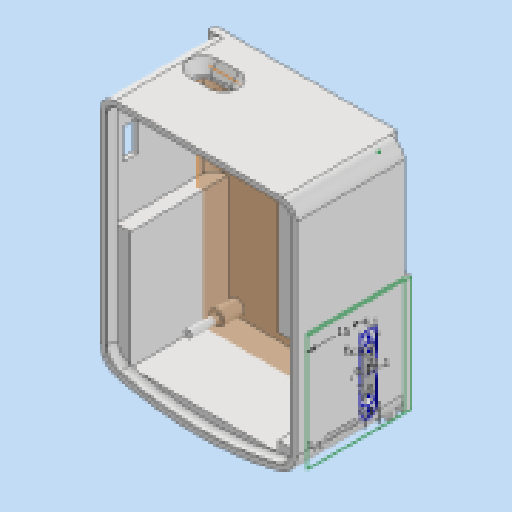
# Autodesk Inventor part: Pieza5
Saved by Autodesk Inventor 2026.3 (Build 303398000, 398)
## iProperties
Created: 2026-11-10
Part Number: Pieza5
Material: Genérico
Document SubType Name: Modeling
Designer: Hp
Density: 1 g/cm^3
Appearance: Valor por defecto
Author: Hp
Autodesk Inventor part; units mm, degrees
(part 1 of 2)
ref_plane "YZ Plane" through (0, 0, 0) normal (1, 0, 0) x (0, 1, 0)
ref_plane "XZ Plane" through (0, 0, 0) normal (0, 1, 0) x (-1, 0, 0)
ref_plane "Plano de trabajo1" through (0, 0, 0) normal (0, 0, 1) x (1, 0, 0)
sketch "Boceto1" plane through (0, 0, 0) normal (0, 0, 1) x (1, 0, 0)
  line L0 (-44, -6) -> (-4, -6)
  line L1 (-44, -66) -> (-44, -6)
  line L2 (-4, -66) -> (-44, -66)
  line L3 (-4, -6) -> (-4, -66)
  circle A0 centre (-40.51, -14.25) radius 0.55
  circle A1 centre (-40.51, -16.79) radius 0.55
  circle A2 centre (-40.51, -19.33) radius 0.55
  circle A3 centre (-40.51, -21.87) radius 0.55
  circle A4 centre (-40.51, -24.41) radius 0.55
  circle A5 centre (-40.51, -26.95) radius 0.55
  circle A6 centre (-40.51, -29.49) radius 0.55
  circle A7 centre (-40.51, -32.03) radius 0.55
  circle A8 centre (-40.51, -34.57) radius 0.55
  circle A9 centre (-40.51, -37.11) radius 0.55
  circle A10 centre (-40.51, -39.65) radius 0.55
  circle A11 centre (-40.51, -42.19) radius 0.55
  circle A12 centre (-40.51, -44.73) radius 0.55
  circle A13 centre (-40.51, -47.27) radius 0.55
  circle A14 centre (-40.51, -49.81) radius 0.55
  circle A15 centre (-40.51, -52.35) radius 0.55
  circle A16 centre (-40.51, -54.89) radius 0.55
  circle A17 centre (-40.51, -57.43) radius 0.55
  circle A18 centre (-40.51, -59.97) radius 0.55
  circle A19 centre (-37.97, -11.71) radius 0.55
  circle A20 centre (-37.97, -14.25) radius 0.55
  circle A21 centre (-37.97, -16.79) radius 0.55
  circle A22 centre (-37.97, -19.33) radius 0.55
  circle A23 centre (-37.97, -21.87) radius 0.55
  circle A24 centre (-37.97, -24.41) radius 0.55
  circle A25 centre (-37.97, -26.95) radius 0.55
  circle A26 centre (-37.97, -29.49) radius 0.55
  circle A27 centre (-37.97, -32.03) radius 0.55
  circle A28 centre (-37.97, -34.57) radius 0.55
  circle A29 centre (-37.97, -37.11) radius 0.55
  circle A30 centre (-37.97, -39.65) radius 0.55
  circle A31 centre (-37.97, -42.19) radius 0.55
  circle A32 centre (-37.97, -44.73) radius 0.55
  circle A33 centre (-37.97, -47.27) radius 0.55
  circle A34 centre (-37.97, -49.81) radius 0.55
  circle A35 centre (-37.97, -52.35) radius 0.55
  circle A36 centre (-37.97, -54.89) radius 0.55
  circle A37 centre (-37.97, -57.43) radius 0.55
  circle A38 centre (-37.97, -59.97) radius 0.55
  circle A39 centre (-35.43, -11.71) radius 0.55
  circle A40 centre (-35.43, -14.25) radius 0.55
  circle A41 centre (-35.43, -16.79) radius 0.55
  circle A42 centre (-35.43, -19.33) radius 0.55
  circle A43 centre (-35.43, -21.87) radius 0.55
  circle A44 centre (-35.43, -24.41) radius 0.55
  circle A45 centre (-35.43, -26.95) radius 0.55
  circle A46 centre (-35.43, -29.49) radius 0.55
  circle A47 centre (-35.43, -32.03) radius 0.55
  circle A48 centre (-35.43, -34.57) radius 0.55
  circle A49 centre (-35.43, -37.11) radius 0.55
  circle A50 centre (-35.43, -39.65) radius 0.55
  circle A51 centre (-35.43, -42.19) radius 0.55
  circle A52 centre (-35.43, -44.73) radius 0.55
  circle A53 centre (-35.43, -47.27) radius 0.55
  circle A54 centre (-35.43, -49.81) radius 0.55
  circle A55 centre (-35.43, -52.35) radius 0.55
  circle A56 centre (-35.43, -54.89) radius 0.55
  circle A57 centre (-35.43, -57.43) radius 0.55
  circle A58 centre (-35.43, -59.97) radius 0.55
  circle A59 centre (-32.89, -11.71) radius 0.55
  circle A60 centre (-32.89, -14.25) radius 0.55
  circle A61 centre (-32.89, -16.79) radius 0.55
  circle A62 centre (-32.89, -19.33) radius 0.55
  circle A63 centre (-32.89, -21.87) radius 0.55
  circle A64 centre (-32.89, -24.41) radius 0.55
  circle A65 centre (-32.89, -26.95) radius 0.55
  circle A66 centre (-32.89, -29.49) radius 0.55
  circle A67 centre (-32.89, -32.03) radius 0.55
  circle A68 centre (-32.89, -34.57) radius 0.55
  circle A69 centre (-32.89, -37.11) radius 0.55
  circle A70 centre (-32.89, -39.65) radius 0.55
  circle A71 centre (-32.89, -42.19) radius 0.55
  circle A72 centre (-32.89, -44.73) radius 0.55
  circle A73 centre (-32.89, -47.27) radius 0.55
  circle A74 centre (-32.89, -49.81) radius 0.55
  circle A75 centre (-32.89, -52.35) radius 0.55
  circle A76 centre (-32.89, -54.89) radius 0.55
  circle A77 centre (-32.89, -57.43) radius 0.55
  circle A78 centre (-32.89, -59.97) radius 0.55
  circle A79 centre (-30.35, -11.71) radius 0.55
  circle A80 centre (-27.81, -11.71) radius 0.55
  circle A81 centre (-25.27, -11.71) radius 0.55
  circle A82 centre (-22.73, -11.71) radius 0.55
  circle A83 centre (-20.19, -11.71) radius 0.55
  circle A84 centre (-17.65, -11.71) radius 0.55
  circle A85 centre (-15.11, -11.71) radius 0.55
  circle A86 centre (-12.57, -11.71) radius 0.55
  circle A87 centre (-10.03, -11.71) radius 0.55
  circle A88 centre (-7.49, -11.71) radius 0.55
  circle A89 centre (-30.35, -14.25) radius 0.55
  circle A90 centre (-27.81, -14.25) radius 0.55
  circle A91 centre (-25.27, -14.25) radius 0.55
  circle A92 centre (-22.73, -14.25) radius 0.55
  circle A93 centre (-20.19, -14.25) radius 0.55
  circle A94 centre (-17.65, -14.25) radius 0.55
  circle A95 centre (-15.11, -14.25) radius 0.55
  circle A96 centre (-12.57, -14.25) radius 0.55
  circle A97 centre (-10.03, -14.25) radius 0.55
  circle A98 centre (-7.49, -14.25) radius 0.55
  circle A99 centre (-30.35, -16.79) radius 0.55
  circle A100 centre (-27.81, -16.79) radius 0.55
  circle A101 centre (-25.27, -16.79) radius 0.55
  circle A102 centre (-22.73, -16.79) radius 0.55
  circle A103 centre (-20.19, -16.79) radius 0.55
  circle A104 centre (-17.65, -16.79) radius 0.55
  circle A105 centre (-15.11, -16.79) radius 0.55
  circle A106 centre (-12.57, -16.79) radius 0.55
  circle A107 centre (-10.03, -16.79) radius 0.55
  circle A108 centre (-7.49, -16.79) radius 0.55
  circle A109 centre (-30.35, -19.33) radius 0.55
  circle A110 centre (-27.81, -19.33) radius 0.55
  circle A111 centre (-25.27, -19.33) radius 0.55
  circle A112 centre (-22.73, -19.33) radius 0.55
  circle A113 centre (-20.19, -19.33) radius 0.55
  circle A114 centre (-17.65, -19.33) radius 0.55
  circle A115 centre (-15.11, -19.33) radius 0.55
  circle A116 centre (-12.57, -19.33) radius 0.55
  circle A117 centre (-10.03, -19.33) radius 0.55
  circle A118 centre (-7.49, -19.33) radius 0.55
  circle A119 centre (-30.35, -21.87) radius 0.55
  circle A120 centre (-27.81, -21.87) radius 0.55
  circle A121 centre (-25.27, -21.87) radius 0.55
  circle A122 centre (-22.73, -21.87) radius 0.55
  circle A123 centre (-20.19, -21.87) radius 0.55
  circle A124 centre (-17.65, -21.87) radius 0.55
  circle A125 centre (-15.11, -21.87) radius 0.55
  circle A126 centre (-12.57, -21.87) radius 0.55
  circle A127 centre (-10.03, -21.87) radius 0.55
  circle A128 centre (-7.49, -21.87) radius 0.55
  circle A129 centre (-30.35, -24.41) radius 0.55
  circle A130 centre (-27.81, -24.41) radius 0.55
  circle A131 centre (-25.27, -24.41) radius 0.55
  circle A132 centre (-22.73, -24.41) radius 0.55
  circle A133 centre (-20.19, -24.41) radius 0.55
  circle A134 centre (-17.65, -24.41) radius 0.55
  circle A135 centre (-15.11, -24.41) radius 0.55
  circle A136 centre (-12.57, -24.41) radius 0.55
  circle A137 centre (-10.03, -24.41) radius 0.55
  circle A138 centre (-7.49, -24.41) radius 0.55
  circle A139 centre (-30.35, -26.95) radius 0.55
  circle A140 centre (-27.81, -26.95) radius 0.55
  circle A141 centre (-25.27, -26.95) radius 0.55
  circle A142 centre (-22.73, -26.95) radius 0.55
  circle A143 centre (-20.19, -26.95) radius 0.55
  circle A144 centre (-17.65, -26.95) radius 0.55
  circle A145 centre (-15.11, -26.95) radius 0.55
  circle A146 centre (-12.57, -26.95) radius 0.55
  circle A147 centre (-10.03, -26.95) radius 0.55
  circle A148 centre (-7.49, -26.95) radius 0.55
  circle A149 centre (-30.35, -29.49) radius 0.55
  circle A150 centre (-27.81, -29.49) radius 0.55
  circle A151 centre (-25.27, -29.49) radius 0.55
  circle A152 centre (-22.73, -29.49) radius 0.55
  circle A153 centre (-20.19, -29.49) radius 0.55
  circle A154 centre (-17.65, -29.49) radius 0.55
  circle A155 centre (-15.11, -29.49) radius 0.55
  circle A156 centre (-12.57, -29.49) radius 0.55
  circle A157 centre (-10.03, -29.49) radius 0.55
  circle A158 centre (-7.49, -29.49) radius 0.55
  circle A159 centre (-30.35, -32.03) radius 0.55
  circle A160 centre (-27.81, -32.03) radius 0.55
  circle A161 centre (-25.27, -32.03) radius 0.55
  circle A162 centre (-22.73, -32.03) radius 0.55
  circle A163 centre (-20.19, -32.03) radius 0.55
  circle A164 centre (-17.65, -32.03) radius 0.55
  circle A165 centre (-15.11, -32.03) radius 0.55
  circle A166 centre (-12.57, -32.03) radius 0.55
  circle A167 centre (-10.03, -32.03) radius 0.55
  circle A168 centre (-7.49, -32.03) radius 0.55
  circle A169 centre (-30.35, -34.57) radius 0.55
  circle A170 centre (-27.81, -34.57) radius 0.55
  circle A171 centre (-25.27, -34.57) radius 0.55
  circle A172 centre (-22.73, -34.57) radius 0.55
  circle A173 centre (-20.19, -34.57) radius 0.55
  circle A174 centre (-17.65, -34.57) radius 0.55
  circle A175 centre (-15.11, -34.57) radius 0.55
  circle A176 centre (-12.57, -34.57) radius 0.55
  circle A177 centre (-10.03, -34.57) radius 0.55
  circle A178 centre (-7.49, -34.57) radius 0.55
  circle A179 centre (-30.35, -37.11) radius 0.55
  circle A180 centre (-27.81, -37.11) radius 0.55
  circle A181 centre (-25.27, -37.11) radius 0.55
  circle A182 centre (-22.73, -37.11) radius 0.55
  circle A183 centre (-20.19, -37.11) radius 0.55
  circle A184 centre (-17.65, -37.11) radius 0.55
  circle A185 centre (-15.11, -37.11) radius 0.55
  circle A186 centre (-12.57, -37.11) radius 0.55
  circle A187 centre (-10.03, -37.11) radius 0.55
  circle A188 centre (-7.49, -37.11) radius 0.55
  circle A189 centre (-30.35, -39.65) radius 0.55
  circle A190 centre (-27.81, -39.65) radius 0.55
  circle A191 centre (-25.27, -39.65) radius 0.55
  circle A192 centre (-22.73, -39.65) radius 0.55
  circle A193 centre (-20.19, -39.65) radius 0.55
  circle A194 centre (-17.65, -39.65) radius 0.55
  circle A195 centre (-15.11, -39.65) radius 0.55
  circle A196 centre (-12.57, -39.65) radius 0.55
  circle A197 centre (-10.03, -39.65) radius 0.55
  circle A198 centre (-7.49, -39.65) radius 0.55
  circle A199 centre (-30.35, -42.19) radius 0.55
  circle A200 centre (-27.81, -42.19) radius 0.55
  circle A201 centre (-25.27, -42.19) radius 0.55
  circle A202 centre (-22.73, -42.19) radius 0.55
  circle A203 centre (-20.19, -42.19) radius 0.55
  circle A204 centre (-17.65, -42.19) radius 0.55
  circle A205 centre (-15.11, -42.19) radius 0.55
  circle A206 centre (-12.57, -42.19) radius 0.55
  circle A207 centre (-10.03, -42.19) radius 0.55
  circle A208 centre (-7.49, -42.19) radius 0.55
  circle A209 centre (-30.35, -44.73) radius 0.55
  circle A210 centre (-27.81, -44.73) radius 0.55
  circle A211 centre (-25.27, -44.73) radius 0.55
  circle A212 centre (-22.73, -44.73) radius 0.55
  circle A213 centre (-20.19, -44.73) radius 0.55
  circle A214 centre (-17.65, -44.73) radius 0.55
  circle A215 centre (-15.11, -44.73) radius 0.55
  circle A216 centre (-12.57, -44.73) radius 0.55
  circle A217 centre (-10.03, -44.73) radius 0.55
  circle A218 centre (-7.49, -44.73) radius 0.55
  circle A219 centre (-30.35, -47.27) radius 0.55
  circle A220 centre (-27.81, -47.27) radius 0.55
  circle A221 centre (-25.27, -47.27) radius 0.55
  circle A222 centre (-22.73, -47.27) radius 0.55
  circle A223 centre (-20.19, -47.27) radius 0.55
  circle A224 centre (-17.65, -47.27) radius 0.55
  circle A225 centre (-15.11, -47.27) radius 0.55
  circle A226 centre (-12.57, -47.27) radius 0.55
  circle A227 centre (-10.03, -47.27) radius 0.55
  circle A228 centre (-7.49, -47.27) radius 0.55
  circle A229 centre (-30.35, -49.81) radius 0.55
  circle A230 centre (-27.81, -49.81) radius 0.55
  circle A231 centre (-25.27, -49.81) radius 0.55
  circle A232 centre (-22.73, -49.81) radius 0.55
  circle A233 centre (-20.19, -49.81) radius 0.55
  circle A234 centre (-17.65, -49.81) radius 0.55
  circle A235 centre (-15.11, -49.81) radius 0.55
  circle A236 centre (-12.57, -49.81) radius 0.55
  circle A237 centre (-10.03, -49.81) radius 0.55
  circle A238 centre (-7.49, -49.81) radius 0.55
  circle A239 centre (-30.35, -52.35) radius 0.55
  circle A240 centre (-27.81, -52.35) radius 0.55
  circle A241 centre (-25.27, -52.35) radius 0.55
  circle A242 centre (-22.73, -52.35) radius 0.55
  circle A243 centre (-20.19, -52.35) radius 0.55
  circle A244 centre (-17.65, -52.35) radius 0.55
  circle A245 centre (-15.11, -52.35) radius 0.55
  circle A246 centre (-12.57, -52.35) radius 0.55
  circle A247 centre (-10.03, -52.35) radius 0.55
  circle A248 centre (-7.49, -52.35) radius 0.55
  circle A249 centre (-30.35, -54.89) radius 0.55
  circle A250 centre (-27.81, -54.89) radius 0.55
  circle A251 centre (-25.27, -54.89) radius 0.55
  circle A252 centre (-22.73, -54.89) radius 0.55
  circle A253 centre (-20.19, -54.89) radius 0.55
  circle A254 centre (-17.65, -54.89) radius 0.55
  circle A255 centre (-15.11, -54.89) radius 0.55
  circle A256 centre (-12.57, -54.89) radius 0.55
  circle A257 centre (-10.03, -54.89) radius 0.55
  circle A258 centre (-7.49, -54.89) radius 0.55
  circle A259 centre (-30.35, -57.43) radius 0.55
  circle A260 centre (-27.81, -57.43) radius 0.55
  circle A261 centre (-25.27, -57.43) radius 0.55
  circle A262 centre (-22.73, -57.43) radius 0.55
  circle A263 centre (-20.19, -57.43) radius 0.55
  circle A264 centre (-17.65, -57.43) radius 0.55
  circle A265 centre (-15.11, -57.43) radius 0.55
  circle A266 centre (-12.57, -57.43) radius 0.55
  circle A267 centre (-10.03, -57.43) radius 0.55
  circle A268 centre (-7.49, -57.43) radius 0.55
  circle A269 centre (-30.35, -59.97) radius 0.55
  circle A270 centre (-27.81, -59.97) radius 0.55
  circle A271 centre (-25.27, -59.97) radius 0.55
  circle A272 centre (-22.73, -59.97) radius 0.55
  circle A273 centre (-20.19, -59.97) radius 0.55
  circle A274 centre (-17.65, -59.97) radius 0.55
  circle A275 centre (-15.11, -59.97) radius 0.55
  circle A276 centre (-12.57, -59.97) radius 0.55
  circle A277 centre (-10.03, -59.97) radius 0.55
  circle A278 centre (-7.49, -59.97) radius 0.55
  circle A279 centre (-42, -8) radius 1.1
  circle A280 centre (-6, -8) radius 1.1
  circle A281 centre (-42, -64) radius 1.1
  circle A282 centre (-6, -64) radius 1.1
  circle A283 centre (-40.51, -11.71) radius 0.55
  line L4 (-3.5, -66.5) -> (-44.5, -66.5)
  line L5 (-44.5, -66.5) -> (-44.5, -5.5)
  line L6 (-44.5, -5.5) -> (-3.5, -5.5)
  line L7 (-3.5, -5.5) -> (-3.5, -66.5)
  line L8 (-35.81, -4.5) -> (-41.59, -4.5)
  line L9 (-35.81, -4.5) -> (-34.49, -4.5)
  line L10 (-34.49, -4.5) -> (-34.49, -11.4)
  line L11 (-42.91, -4.5) -> (-42.91, -11.4)
  line L12 (-42.91, -4.5) -> (-41.59, -4.5)
  line L13 (-44.9, -5.5) -> (-47.4, -5.5)
  line L14 (-47.4, -5.5) -> (-47.4, -33.8)
  line L15 (-47.4, -33.8) -> (-45.4, -33.8)
  line L16 (-44.5, -5.5) -> (-44.9, -5.5)
  line L17 (-45.4, -33.8) -> (-44.5, -33.8)
  line L18 (-43.91, -11.4) -> (-43.91, -3.5)
  line L19 (-43.91, -3.5) -> (-41.59, -3.5)
  line L20 (-41.59, -3.5) -> (-35.81, -3.5)
  line L21 (-35.81, -3.5) -> (-33.49, -3.5)
  line L22 (-33.49, -3.5) -> (-33.49, -11.4)
  line L23 (-46.5, -3.5) -> (-46.5, -68.5)
  line L24 (-46.5, -68.5) -> (-1.5, -68.5)
  line L25 (-1.5, -68.5) -> (-1.5, -3.5)
  line L26 (-1.5, -3.5) -> (-46.5, -3.5)
  line L27 (-44.5, -36.3) -> (-45.4, -36.3)
  line L28 (-45.4, -36.3) -> (-49.9, -36.3)
  line L29 (-49.9, -36.3) -> (-49.9, -3)
  line L30 (-49.9, -3) -> (-44.9, -3)
  line L31 (-44.9, -3) -> (-44.5, -3)
  line L32 (-48.5, -70.5) -> (-48.5, -1.5)
  line L33 (-48.5, -1.5) -> (0.5, -1.5)
  line L34 (0.5, -1.5) -> (0.5, -70.5)
  line L35 (0.5, -70.5) -> (-48.5, -70.5)
  line L36 (-33.49, -3.5) -> (-33.49, -1.5)
  line L37 (-43.91, -3.5) -> (-43.91, -1.5)
  line L38 (-44.5, -3) -> (-43.91, -3)
  line L39 (-3.5, -63.5) -> (1.5, -63.5)
  line L40 (1.5, -63.5) -> (1.5, -37.5)
  line L41 (1.5, -37.5) -> (-3.5, -37.5)
  line L42 (-3.5, -37.5) -> (-3.5, -63.5)
  line L43 (4.5, -66.5) -> (-6.5, -66.5)
  line L44 (-6.5, -66.5) -> (-6.5, -34.5)
  line L45 (-6.5, -34.5) -> (4.5, -34.5)
  line L46 (4.5, -34.5) -> (4.5, -66.5)
  line L47 (-46.5, -5.5) -> (-48.5, -5.5)
  line L48 (-47.4, -33.8) -> (-49.9, -33.8)
  line L49 (-48.5, -1.5) -> (-49.9, -1.5)
  line L50 (-49.9, -1.5) -> (-49.9, -3)
  point P0 (0, 0)
  point P1 (-46.5, -5)
  point P2 (-43.91, -3.5)
  point P3 (-33.49, -5.5)
  point P4 (-44.5, -36.3)
  point P5 (-42.91, -5.5)
  point P6 (-34.49, -5.5)
  point P7 (0.5, -66.5)
  point P8 (0.5, -34.5)
  point P9 (0.5, -37.5)
  point P10 (0.5, -63.5)
  point P11 (-48.5, -36.3)
  point P12 (-48.5, -3)
  point P13 (-43.91, -5.5)
  point P14 (-1.5, -66.5)
  point P15 (-46.5, -36.3)
  point P16 (-3.5, -66.5)
  point P17 (-3.5, -37.5)
  point P18 (-3.5, -34.5)
  point P19 (-1.5, -34.5)
  point P20 (-1.5, -63.5)
  point P21 (-1.5, -37.5)
  point P22 (-46.5, -33.8)
  point P23 (-48.5, -33.8)
extrude "Extrusión1" add sketch "Boceto1" along normal blind 20 and the other way blind 8 contours L18 L19 L20 L21 L22 L6 L10 L9 L8 L12 L11 | L6 L16 L13 L23 L26 L18 | L11 L12 L8 L9 L10 L6 | L37 L33 L36 L21 L20 L19 | L26 L23 L13 L47 L32 L30 L31 L38 L37 | L4 L43 L25 L24 L23 L28 L27 L5 | L5 L27 L28 L23 L15 L17 | L38 L31 L30 L32 L33 L37 | L7 L39 L25 L43 | L22 L26 L25 L45 L7 L6 | L45 L25 L41 L7 | L43 L34 L35 L32 L28 L23 L24 L25 | L25 L39 L34 L43 | L36 L33 L34 L45 L25 L26 | L23 L28 L32 L48 L15 | L32 L30 L50 L49 | L45 L34 L41 L25 | L34 L39 L40 L41 L45 L46 L43 | L32 L48 L29 L30 | L34 L41 L40 L39 | L28 L29 L48 L32
sketch "Boceto3" plane through (0, 0, -8) normal (0, 0, 1) x (1, 0, 0)
  line L0 (-44, -6) -> (-4, -6) projected
  line L1 (-44, -66) -> (-44, -6) projected
  line L2 (-4, -66) -> (-44, -66) projected
  line L3 (-4, -6) -> (-4, -66) projected
  circle A0 centre (-40.51, -14.25) radius 0.55 projected
  circle A1 centre (-40.51, -16.79) radius 0.55 projected
  circle A2 centre (-40.51, -19.33) radius 0.55 projected
  circle A3 centre (-40.51, -21.87) radius 0.55 projected
  circle A4 centre (-40.51, -24.41) radius 0.55 projected
  circle A5 centre (-40.51, -26.95) radius 0.55 projected
  circle A6 centre (-40.51, -29.49) radius 0.55 projected
  circle A7 centre (-40.51, -32.03) radius 0.55 projected
  circle A8 centre (-40.51, -34.57) radius 0.55 projected
  circle A9 centre (-40.51, -37.11) radius 0.55 projected
  circle A10 centre (-40.51, -39.65) radius 0.55 projected
  circle A11 centre (-40.51, -42.19) radius 0.55 projected
  circle A12 centre (-40.51, -44.73) radius 0.55 projected
  circle A13 centre (-40.51, -47.27) radius 0.55 projected
  circle A14 centre (-40.51, -49.81) radius 0.55 projected
  circle A15 centre (-40.51, -52.35) radius 0.55 projected
  circle A16 centre (-40.51, -54.89) radius 0.55 projected
  circle A17 centre (-40.51, -57.43) radius 0.55 projected
  circle A18 centre (-40.51, -59.97) radius 0.55 projected
  circle A19 centre (-37.97, -11.71) radius 0.55 projected
  circle A20 centre (-37.97, -14.25) radius 0.55 projected
  circle A21 centre (-37.97, -16.79) radius 0.55 projected
  circle A22 centre (-37.97, -19.33) radius 0.55 projected
  circle A23 centre (-37.97, -21.87) radius 0.55 projected
  circle A24 centre (-37.97, -24.41) radius 0.55 projected
  circle A25 centre (-37.97, -26.95) radius 0.55 projected
  circle A26 centre (-37.97, -29.49) radius 0.55 projected
  circle A27 centre (-37.97, -32.03) radius 0.55 projected
  circle A28 centre (-37.97, -34.57) radius 0.55 projected
  circle A29 centre (-37.97, -37.11) radius 0.55 projected
  circle A30 centre (-37.97, -39.65) radius 0.55 projected
  circle A31 centre (-37.97, -42.19) radius 0.55 projected
  circle A32 centre (-37.97, -44.73) radius 0.55 projected
  circle A33 centre (-37.97, -47.27) radius 0.55 projected
  circle A34 centre (-37.97, -49.81) radius 0.55 projected
  circle A35 centre (-37.97, -52.35) radius 0.55 projected
  circle A36 centre (-37.97, -54.89) radius 0.55 projected
  circle A37 centre (-37.97, -57.43) radius 0.55 projected
  circle A38 centre (-37.97, -59.97) radius 0.55 projected
  circle A39 centre (-35.43, -11.71) radius 0.55 projected
  circle A40 centre (-35.43, -14.25) radius 0.55 projected
  circle A41 centre (-35.43, -16.79) radius 0.55 projected
  circle A42 centre (-35.43, -19.33) radius 0.55 projected
  circle A43 centre (-35.43, -21.87) radius 0.55 projected
  circle A44 centre (-35.43, -24.41) radius 0.55 projected
  circle A45 centre (-35.43, -26.95) radius 0.55 projected
  circle A46 centre (-35.43, -29.49) radius 0.55 projected
  circle A47 centre (-35.43, -32.03) radius 0.55 projected
  circle A48 centre (-35.43, -34.57) radius 0.55 projected
  circle A49 centre (-35.43, -37.11) radius 0.55 projected
  circle A50 centre (-35.43, -39.65) radius 0.55 projected
  circle A51 centre (-35.43, -42.19) radius 0.55 projected
  circle A52 centre (-35.43, -44.73) radius 0.55 projected
  circle A53 centre (-35.43, -47.27) radius 0.55 projected
  circle A54 centre (-35.43, -49.81) radius 0.55 projected
  circle A55 centre (-35.43, -52.35) radius 0.55 projected
  circle A56 centre (-35.43, -54.89) radius 0.55 projected
  circle A57 centre (-35.43, -57.43) radius 0.55 projected
  circle A58 centre (-35.43, -59.97) radius 0.55 projected
  circle A59 centre (-32.89, -11.71) radius 0.55 projected
  circle A60 centre (-32.89, -14.25) radius 0.55 projected
  circle A61 centre (-32.89, -16.79) radius 0.55 projected
  circle A62 centre (-32.89, -19.33) radius 0.55 projected
  circle A63 centre (-32.89, -21.87) radius 0.55 projected
  circle A64 centre (-32.89, -24.41) radius 0.55 projected
  circle A65 centre (-32.89, -26.95) radius 0.55 projected
  circle A66 centre (-32.89, -29.49) radius 0.55 projected
  circle A67 centre (-32.89, -32.03) radius 0.55 projected
  circle A68 centre (-32.89, -34.57) radius 0.55 projected
  circle A69 centre (-32.89, -37.11) radius 0.55 projected
  circle A70 centre (-32.89, -39.65) radius 0.55 projected
  circle A71 centre (-32.89, -42.19) radius 0.55 projected
  circle A72 centre (-32.89, -44.73) radius 0.55 projected
  circle A73 centre (-32.89, -47.27) radius 0.55 projected
  circle A74 centre (-32.89, -49.81) radius 0.55 projected
  circle A75 centre (-32.89, -52.35) radius 0.55 projected
  circle A76 centre (-32.89, -54.89) radius 0.55 projected
  circle A77 centre (-32.89, -57.43) radius 0.55 projected
  circle A78 centre (-32.89, -59.97) radius 0.55 projected
  circle A79 centre (-30.35, -11.71) radius 0.55 projected
  circle A80 centre (-27.81, -11.71) radius 0.55 projected
  circle A81 centre (-25.27, -11.71) radius 0.55 projected
  circle A82 centre (-22.73, -11.71) radius 0.55 projected
  circle A83 centre (-20.19, -11.71) radius 0.55 projected
  circle A84 centre (-17.65, -11.71) radius 0.55 projected
  circle A85 centre (-15.11, -11.71) radius 0.55 projected
  circle A86 centre (-12.57, -11.71) radius 0.55 projected
  circle A87 centre (-10.03, -11.71) radius 0.55 projected
  circle A88 centre (-7.49, -11.71) radius 0.55 projected
  circle A89 centre (-30.35, -14.25) radius 0.55 projected
  circle A90 centre (-27.81, -14.25) radius 0.55 projected
  circle A91 centre (-25.27, -14.25) radius 0.55 projected
  circle A92 centre (-22.73, -14.25) radius 0.55 projected
  circle A93 centre (-20.19, -14.25) radius 0.55 projected
  circle A94 centre (-17.65, -14.25) radius 0.55 projected
  circle A95 centre (-15.11, -14.25) radius 0.55 projected
  circle A96 centre (-12.57, -14.25) radius 0.55 projected
  circle A97 centre (-10.03, -14.25) radius 0.55 projected
  circle A98 centre (-7.49, -14.25) radius 0.55 projected
  circle A99 centre (-30.35, -16.79) radius 0.55 projected
  circle A100 centre (-27.81, -16.79) radius 0.55 projected
  circle A101 centre (-25.27, -16.79) radius 0.55 projected
  circle A102 centre (-22.73, -16.79) radius 0.55 projected
  circle A103 centre (-20.19, -16.79) radius 0.55 projected
  circle A104 centre (-17.65, -16.79) radius 0.55 projected
  circle A105 centre (-15.11, -16.79) radius 0.55 projected
  circle A106 centre (-12.57, -16.79) radius 0.55 projected
  circle A107 centre (-10.03, -16.79) radius 0.55 projected
  circle A108 centre (-7.49, -16.79) radius 0.55 projected
  circle A109 centre (-30.35, -19.33) radius 0.55 projected
  circle A110 centre (-27.81, -19.33) radius 0.55 projected
  circle A111 centre (-25.27, -19.33) radius 0.55 projected
  circle A112 centre (-22.73, -19.33) radius 0.55 projected
  circle A113 centre (-20.19, -19.33) radius 0.55 projected
  circle A114 centre (-17.65, -19.33) radius 0.55 projected
  circle A115 centre (-15.11, -19.33) radius 0.55 projected
  circle A116 centre (-12.57, -19.33) radius 0.55 projected
  circle A117 centre (-10.03, -19.33) radius 0.55 projected
  circle A118 centre (-7.49, -19.33) radius 0.55 projected
  circle A119 centre (-30.35, -21.87) radius 0.55 projected
  circle A120 centre (-27.81, -21.87) radius 0.55 projected
  circle A121 centre (-25.27, -21.87) radius 0.55 projected
  circle A122 centre (-22.73, -21.87) radius 0.55 projected
  circle A123 centre (-20.19, -21.87) radius 0.55 projected
  circle A124 centre (-17.65, -21.87) radius 0.55 projected
  circle A125 centre (-15.11, -21.87) radius 0.55 projected
  circle A126 centre (-12.57, -21.87) radius 0.55 projected
  circle A127 centre (-10.03, -21.87) radius 0.55 projected
  circle A128 centre (-7.49, -21.87) radius 0.55 projected
  circle A129 centre (-30.35, -24.41) radius 0.55 projected
  circle A130 centre (-27.81, -24.41) radius 0.55 projected
  circle A131 centre (-25.27, -24.41) radius 0.55 projected
  circle A132 centre (-22.73, -24.41) radius 0.55 projected
  circle A133 centre (-20.19, -24.41) radius 0.55 projected
  circle A134 centre (-17.65, -24.41) radius 0.55 projected
  circle A135 centre (-15.11, -24.41) radius 0.55 projected
  circle A136 centre (-12.57, -24.41) radius 0.55 projected
  circle A137 centre (-10.03, -24.41) radius 0.55 projected
  circle A138 centre (-7.49, -24.41) radius 0.55 projected
  circle A139 centre (-30.35, -26.95) radius 0.55 projected
  circle A140 centre (-27.81, -26.95) radius 0.55 projected
  circle A141 centre (-25.27, -26.95) radius 0.55 projected
  circle A142 centre (-22.73, -26.95) radius 0.55 projected
  circle A143 centre (-20.19, -26.95) radius 0.55 projected
  circle A144 centre (-17.65, -26.95) radius 0.55 projected
  circle A145 centre (-15.11, -26.95) radius 0.55 projected
  circle A146 centre (-12.57, -26.95) radius 0.55 projected
  circle A147 centre (-10.03, -26.95) radius 0.55 projected
  circle A148 centre (-7.49, -26.95) radius 0.55 projected
  circle A149 centre (-30.35, -29.49) radius 0.55 projected
  circle A150 centre (-27.81, -29.49) radius 0.55 projected
  circle A151 centre (-25.27, -29.49) radius 0.55 projected
  circle A152 centre (-22.73, -29.49) radius 0.55 projected
  circle A153 centre (-20.19, -29.49) radius 0.55 projected
  circle A154 centre (-17.65, -29.49) radius 0.55 projected
  circle A155 centre (-15.11, -29.49) radius 0.55 projected
  circle A156 centre (-12.57, -29.49) radius 0.55 projected
  circle A157 centre (-10.03, -29.49) radius 0.55 projected
  circle A158 centre (-7.49, -29.49) radius 0.55 projected
  circle A159 centre (-30.35, -32.03) radius 0.55 projected
  circle A160 centre (-27.81, -32.03) radius 0.55 projected
  circle A161 centre (-25.27, -32.03) radius 0.55 projected
  circle A162 centre (-22.73, -32.03) radius 0.55 projected
  circle A163 centre (-20.19, -32.03) radius 0.55 projected
  circle A164 centre (-17.65, -32.03) radius 0.55 projected
  circle A165 centre (-15.11, -32.03) radius 0.55 projected
  circle A166 centre (-12.57, -32.03) radius 0.55 projected
  circle A167 centre (-10.03, -32.03) radius 0.55 projected
  circle A168 centre (-7.49, -32.03) radius 0.55 projected
  circle A169 centre (-30.35, -34.57) radius 0.55 projected
  circle A170 centre (-27.81, -34.57) radius 0.55 projected
  circle A171 centre (-25.27, -34.57) radius 0.55 projected
  circle A172 centre (-22.73, -34.57) radius 0.55 projected
  circle A173 centre (-20.19, -34.57) radius 0.55 projected
  circle A174 centre (-17.65, -34.57) radius 0.55 projected
  circle A175 centre (-15.11, -34.57) radius 0.55 projected
  circle A176 centre (-12.57, -34.57) radius 0.55 projected
  circle A177 centre (-10.03, -34.57) radius 0.55 projected
  circle A178 centre (-7.49, -34.57) radius 0.55 projected
  circle A179 centre (-30.35, -37.11) radius 0.55 projected
  circle A180 centre (-27.81, -37.11) radius 0.55 projected
  circle A181 centre (-25.27, -37.11) radius 0.55 projected
  circle A182 centre (-22.73, -37.11) radius 0.55 projected
  circle A183 centre (-20.19, -37.11) radius 0.55 projected
  circle A184 centre (-17.65, -37.11) radius 0.55 projected
  circle A185 centre (-15.11, -37.11) radius 0.55 projected
  circle A186 centre (-12.57, -37.11) radius 0.55 projected
  circle A187 centre (-10.03, -37.11) radius 0.55 projected
  circle A188 centre (-7.49, -37.11) radius 0.55 projected
  circle A189 centre (-30.35, -39.65) radius 0.55 projected
  circle A190 centre (-27.81, -39.65) radius 0.55 projected
  circle A191 centre (-25.27, -39.65) radius 0.55 projected
  circle A192 centre (-22.73, -39.65) radius 0.55 projected
  circle A193 centre (-20.19, -39.65) radius 0.55 projected
  circle A194 centre (-17.65, -39.65) radius 0.55 projected
  circle A195 centre (-15.11, -39.65) radius 0.55 projected
  circle A196 centre (-12.57, -39.65) radius 0.55 projected
  circle A197 centre (-10.03, -39.65) radius 0.55 projected
  circle A198 centre (-7.49, -39.65) radius 0.55 projected
  circle A199 centre (-30.35, -42.19) radius 0.55 projected
  circle A200 centre (-27.81, -42.19) radius 0.55 projected
  circle A201 centre (-25.27, -42.19) radius 0.55 projected
  circle A202 centre (-22.73, -42.19) radius 0.55 projected
  circle A203 centre (-20.19, -42.19) radius 0.55 projected
  circle A204 centre (-17.65, -42.19) radius 0.55 projected
  circle A205 centre (-15.11, -42.19) radius 0.55 projected
  circle A206 centre (-12.57, -42.19) radius 0.55 projected
  circle A207 centre (-10.03, -42.19) radius 0.55 projected
  circle A208 centre (-7.49, -42.19) radius 0.55 projected
  circle A209 centre (-30.35, -44.73) radius 0.55 projected
  circle A210 centre (-27.81, -44.73) radius 0.55 projected
  circle A211 centre (-25.27, -44.73) radius 0.55 projected
  circle A212 centre (-22.73, -44.73) radius 0.55 projected
  circle A213 centre (-20.19, -44.73) radius 0.55 projected
  circle A214 centre (-17.65, -44.73) radius 0.55 projected
  circle A215 centre (-15.11, -44.73) radius 0.55 projected
  circle A216 centre (-12.57, -44.73) radius 0.55 projected
  circle A217 centre (-10.03, -44.73) radius 0.55 projected
  circle A218 centre (-7.49, -44.73) radius 0.55 projected
  circle A219 centre (-30.35, -47.27) radius 0.55 projected
  circle A220 centre (-27.81, -47.27) radius 0.55 projected
  circle A221 centre (-25.27, -47.27) radius 0.55 projected
  circle A222 centre (-22.73, -47.27) radius 0.55 projected
  circle A223 centre (-20.19, -47.27) radius 0.55 projected
  circle A224 centre (-17.65, -47.27) radius 0.55 projected
  circle A225 centre (-15.11, -47.27) radius 0.55 projected
  circle A226 centre (-12.57, -47.27) radius 0.55 projected
  circle A227 centre (-10.03, -47.27) radius 0.55 projected
  circle A228 centre (-7.49, -47.27) radius 0.55 projected
  circle A229 centre (-30.35, -49.81) radius 0.55 projected
  circle A230 centre (-27.81, -49.81) radius 0.55 projected
  circle A231 centre (-25.27, -49.81) radius 0.55 projected
  circle A232 centre (-22.73, -49.81) radius 0.55 projected
  circle A233 centre (-20.19, -49.81) radius 0.55 projected
  circle A234 centre (-17.65, -49.81) radius 0.55 projected
  circle A235 centre (-15.11, -49.81) radius 0.55 projected
  circle A236 centre (-12.57, -49.81) radius 0.55 projected
  circle A237 centre (-10.03, -49.81) radius 0.55 projected
  circle A238 centre (-7.49, -49.81) radius 0.55 projected
  circle A239 centre (-30.35, -52.35) radius 0.55 projected
  circle A240 centre (-27.81, -52.35) radius 0.55 projected
  circle A241 centre (-25.27, -52.35) radius 0.55 projected
  circle A242 centre (-22.73, -52.35) radius 0.55 projected
  circle A243 centre (-20.19, -52.35) radius 0.55 projected
  circle A244 centre (-17.65, -52.35) radius 0.55 projected
  circle A245 centre (-15.11, -52.35) radius 0.55 projected
  circle A246 centre (-12.57, -52.35) radius 0.55 projected
  circle A247 centre (-10.03, -52.35) radius 0.55 projected
  circle A248 centre (-7.49, -52.35) radius 0.55 projected
  circle A249 centre (-30.35, -54.89) radius 0.55 projected
  circle A250 centre (-27.81, -54.89) radius 0.55 projected
  circle A251 centre (-25.27, -54.89) radius 0.55 projected
  circle A252 centre (-22.73, -54.89) radius 0.55 projected
  circle A253 centre (-20.19, -54.89) radius 0.55 projected
  circle A254 centre (-17.65, -54.89) radius 0.55 projected
  circle A255 centre (-15.11, -54.89) radius 0.55 projected
  circle A256 centre (-12.57, -54.89) radius 0.55 projected
  circle A257 centre (-10.03, -54.89) radius 0.55 projected
  circle A258 centre (-7.49, -54.89) radius 0.55 projected
  circle A259 centre (-30.35, -57.43) radius 0.55 projected
  circle A260 centre (-27.81, -57.43) radius 0.55 projected
  circle A261 centre (-25.27, -57.43) radius 0.55 projected
  circle A262 centre (-22.73, -57.43) radius 0.55 projected
  circle A263 centre (-20.19, -57.43) radius 0.55 projected
  circle A264 centre (-17.65, -57.43) radius 0.55 projected
  circle A265 centre (-15.11, -57.43) radius 0.55 projected
  circle A266 centre (-12.57, -57.43) radius 0.55 projected
  circle A267 centre (-10.03, -57.43) radius 0.55 projected
  circle A268 centre (-7.49, -57.43) radius 0.55 projected
  circle A269 centre (-30.35, -59.97) radius 0.55 projected
  circle A270 centre (-27.81, -59.97) radius 0.55 projected
  circle A271 centre (-25.27, -59.97) radius 0.55 projected
  circle A272 centre (-22.73, -59.97) radius 0.55 projected
  circle A273 centre (-20.19, -59.97) radius 0.55 projected
  circle A274 centre (-17.65, -59.97) radius 0.55 projected
  circle A275 centre (-15.11, -59.97) radius 0.55 projected
  circle A276 centre (-12.57, -59.97) radius 0.55 projected
  circle A277 centre (-10.03, -59.97) radius 0.55 projected
  circle A278 centre (-7.49, -59.97) radius 0.55 projected
  circle A279 centre (-42, -8) radius 1.1 projected
  circle A280 centre (-6, -8) radius 1.1 projected
  circle A281 centre (-42, -64) radius 1.1 projected
  circle A282 centre (-6, -64) radius 1.1 projected
  circle A283 centre (-40.51, -11.71) radius 0.55 projected
  line L4 (-48.5, -70.5) -> (0.5, -70.5) projected
  line L5 (0.5, -70.5) -> (0.5, -66.5) projected
  line L6 (-33.49, -5.5) -> (-33.49, -6)
  line L7 (-44.5, -34.3) -> (-44.5, -5)
  line L8 (-33.49, -5.5) -> (-44.5, -5.5)
  line L9 (-43.91, -5) -> (-43.91, -5.5)
  circle A284 centre (-42, -64) radius 1
  circle A285 centre (-6, -64) radius 1
  circle A286 centre (-6, -8) radius 1
  line L10 (-49.9, -36.3) -> (-48.5, -36.3) projected
  line L11 (-48.5, -36.3) -> (-48.5, -70.5) projected
  line L12 (-48.5, -33.8) -> (-48.5, -5.5) projected
  line L13 (-48.5, -5.5) -> (-3.5, -5.5) projected
  line L14 (-3.5, -5.5) -> (-3.5, -37.5) projected
  line L15 (-3.5, -66.5) -> (-44.5, -66.5) projected
  line L16 (-44.5, -66.5) -> (-44.5, -33.8) projected
  line L17 (-44.5, -33.8) -> (-48.5, -33.8) projected
  line L18 (-3.5, -37.5) -> (0.5, -37.5) projected
  line L19 (0.5, -63.5) -> (-3.5, -63.5) projected
  line L20 (-3.5, -63.5) -> (-3.5, -66.5) projected
  line L21 (0.5, -66.5) -> (4.5, -66.5) projected
  line L22 (4.5, -66.5) -> (4.5, -34.5) projected
  line L23 (4.5, -34.5) -> (0.5, -34.5) projected
  line L24 (0.5, -34.5) -> (0.5, -1.5) projected
  line L25 (0.5, -37.5) -> (0.5, -63.5) projected
  line L26 (0.5, -1.5) -> (-49.9, -1.5) projected
  line L27 (-49.9, -1.5) -> (-49.9, -36.3) projected
  point P0 (0, 0)
  dimension "d38" = 0.1
  constraints: 8 end point, 3 centre point, 3 perpendicular, 3 point on line, 2 equal radius
  measures "d38" radial gap between concentric circles of A281 A284
extrude "Extrusión2" add sketch "Boceto3" along normal blind 1 contours L0 L3 L2 L1 | A0 | A1 | A2 | A3 | A4 | A5 | A6 | A7 | A8 | A9 | A10 | A11 | A12 | A13 | A14 | A15 | A16 | A17 | A18 | A19 | A20 | A21 | A22 | A23 | A24 | A25 | A26 | A27 | A28 | A29 | A30 | A31 | A32 | A33 | A34 | A35 | A36 | A37 | A38 | A39 | A40 | A41 | A42 | A43 | A44 | A45 | A46 | A47 | A48 | A49 | A50 | A51 | A52 | A53 | A54 | A55 | A56 | A57 | A58 | A59 | A60 | A61 | A62 | A63 | A64 | A65 | A66 | A67 | A68 | A69 | A70 | A71 | A72 | A73 | A74 | A75 | A76 | A77 | A78 | A79 | A80 | A81 | A82 | A83 | A84 | A85 | A86 | A87 | A88 | A89 | A90 | A91 | A92 | A93 | A94 | A95 | A96 | A97 | A98 | A99 | A100 | A101 | A102 | A103 | A104 | A105 | A106 | A107 | A108 | A109 | A110 | A111 | A112 | A113 | A114 | A115 | A116 | A117 | A118 | A119 | A120 | A121 | A122 | A123 | A124 | A125 | A126 | A127 | A128 | A129 | A130 | A131 | A132 | A133 | A134 | A135 | A136 | A137 | A138 | A139 | A140 | A141 | A142 | A143 | A144 | A145 | A146 | A147 | A148 | A149 | A150 | A151 | A152 | A153 | A154 | A155 | A156 | A157 | A158 | A159 | A160 | A161 | A162 | A163 | A164 | A165 | A166 | A167 | A168 | A169 | A170 | A171 | A172 | A173 | A174 | A175 | A176 | A177 | A178 | A179 | A180 | A181 | A182 | A183 | A184 | A185 | A186 | A187 | A188 | A189 | A190 | A191 | A192 | A193 | A194 | A195 | A196 | A197 | A198 | A199 | A200 | A201 | A202 | A203 | A204 | A205 | A206 | A207 | A208 | A209 | A210 | A211 | A212 | A213 | A214 | A215 | A216 | A217 | A218 | A219 | A220 | A221 | A222 | A223 | A224 | A225 | A226 | A227 | A228 | A229 | A230 | A231 | A232 | A233 | A234 | A235 | A236 | A237 | A238 | A239 | A240 | A241 | A242 | A243 | A244 | A245 | A246 | A247 | A248 | A249 | A250 | A251 | A252 | A253 | A254 | A255 | A256 | A257 | A258 | A259 | A260 | A261 | A262 | A263 | A264 | A265 | A266 | A267 | A268 | A269 | A270 | A271 | A272 | A273 | A274 | A275 | A276 | A277 | A278 | A279 | A280 | A281 | A282 | A283 | L11 L10 L27 L26 L24 L23 L22 L21 L5 L4 | L7 L8 L13 L14 L18 L25 L19 L20 L15 L16 | L17 L12 L13 L7 | A284 | A285 | A286
sketch "Boceto6" plane through (4.5, -71.5, 20) normal (1, 0, 0) x (0, 0, -1)
  line L0 (27, 5) -> (0, 5) projected
  line L1 (27, 5) -> (0, 5) projected
  line L2 (27, 5) -> (27, 37.7) projected
  line L3 (0, 5) -> (0, 37.7) projected
  line L4 (27, 5) -> (0, 5) projected
  line L5 (15, 9) -> (19.1, 9) construction
  line L6 (19.1, 9) -> (19.1, 11.05) construction
  line L7 (19.1, 30.1) -> (15, 30.1) construction
  line L8 (15, 30.1) -> (15, 11.05) construction
  line L9 (15, 12) -> (19.1, 12) construction
  line L10 (19.1, 27) -> (15, 27) construction
  arc A0 (15, 14.05) -> (19.1, 14.05) centre (17.05, 14.05) ccw construction
  arc A1 (15, 11.05) -> (19.1, 11.05) centre (17.05, 11.05) ccw construction
  circle A2 centre (17.05, 10.5) radius 0.5 construction
  line L11 (19.1, 19.5) -> (15, 19.5) construction
  line L12 (15, 11.05) -> (15, 9) construction
  line L13 (19.1, 11.05) -> (19.1, 30.1) construction
  circle A3 centre (17.05, 10.5) radius 0.4
  arc A4 (19.1, 24.95) -> (15, 24.95) centre (17.05, 24.95) ccw construction
  arc A5 (19.1, 27.95) -> (15, 27.95) centre (17.05, 27.95) ccw construction
  circle A6 centre (17.05, 28.5) radius 0.4
  line L14 (28, 37) -> (0, 37) projected
  line L15 (0, 5) -> (0, 37) projected
  line L16 (28, 5) -> (0, 5) projected
  line L17 (28, 37) -> (28, 5) projected
  line L18 (0, 37.7) -> (27, 37.7) projected
  arc A7 (14.9, 11.05) -> (19.2, 11.05) centre (17.05, 11.05) ccw
  line L19 (19.2, 11.05) -> (19.2, 30.2)
  line L20 (19.2, 30.2) -> (14.9, 30.2) construction
  line L21 (14.9, 30.2) -> (14.9, 11.05)
  arc A8 (19.2, 27.95) -> (14.9, 27.95) centre (17.05, 27.95) ccw
  arc A9 (14.9, 14.05) -> (19.2, 14.05) centre (17.05, 14.05) ccw
  arc A10 (19.2, 24.95) -> (14.9, 24.95) centre (17.05, 24.95) ccw
  point P0 (20, 71.5)
  point P1 (17.05, 9)
  point P2 (15, 24.95)
  point P3 (19.1, 24.95)
  point P4 (27, 37)
  point P5 (19.2, 27.95)
  point P6 (14.9, 27.95)
  point P7 (14.9, 14.05)
  point P8 (14.9, 24.95)
  point P9 (19.2, 24.95)
  point P10 (19.2, 14.05)
  dimension "d28" = 4.1
  dimension "d29" = 21.1
  dimension "d30" = 15
  dimension "d31" = 4
  dimension "d32" = 15
  dimension "d33" = 3
  dimension "d34" = 1
  dimension "d35" = 1.5
  dimension "d36" = 7.5
  dimension "d37" = 0.1
  dimension "d62" = 0.1
  dimension "d64" = 0.1
  constraints: 24 end point, 17 point on circle, 12 point on line, 11 centre point, 10 tangent, 8 perpendicular, 7 symmetric about line, 6 parallel, 2 equal radius, 1 horizontal, 1 vertical alignment, 6 other
  measures "d28" distance of L7.start L7.end
  measures "d29" distance of L5.end L7.start
  measures "d30" distance between parallel lines of L3 L8
  measures "d31" distance between parallel lines of L0 L5
  measures "d32" distance between parallel lines of L10 L9
  measures "d33" distance between parallel lines of L5 L9
  measures "d34" diameter of A2
  measures "d35" distance of point (17.05, 9) A2.centre
  measures "d36" distance between parallel lines of L9 L11
  measures "d37" radial gap between concentric circles of A2 A3
  measures "d62" distance between parallel lines of L8 L21
  measures "d64" radial gap between concentric circles of A10 A4
extrude "Extrusión3" cut sketch "Boceto6" against normal blind 6 contours A3 | A6 | L21 A9 L19 A7 | L21 A10 L19 A9 | L21 A8 L19 A10
extrude "Extrusión4" add sketch "Boceto6" against normal blind 2 contours L0 L3 L14 L2 | L2 L14 L17 L16 | A3 | A6 | L21 A9 L19 A7 | L21 A8 L19 A10
ref_plane "Plano de trabajo2" through (-44, -66, -1.5) normal (0, 0, -1) x (0, 1, 0)
sketch "Boceto8" plane through (0, 0, -7) normal (0, 0, 1) x (1, 0, 0)
  circle A0 centre (-42, -64) radius 1.05 projected
  circle A1 centre (-6, -64) radius 1.05 projected
  circle A2 centre (-6, -8) radius 1.05 projected
  circle A3 centre (-42, -64) radius 2
  circle A4 centre (-6, -64) radius 2
  circle A5 centre (-6, -8) radius 2
  line L0 (-39, -12.5) -> (-39, -12.5)
  line L1 (-42, -15.5) -> (-42, -24.5)
  line L2 (-39, -27.5) -> (-39, -27.5)
  line L3 (-36, -24.5) -> (-36, -15.5)
  line L4 (-48.5, -5.5) -> (-3.5, -5.5) projected
  arc A6 (-39, -27.5) -> (-36, -24.5) centre (-39, -24.5) ccw
  arc A7 (-42, -24.5) -> (-39, -27.5) centre (-39, -24.5) ccw
  arc A8 (-39, -12.5) -> (-42, -15.5) centre (-39, -15.5) ccw
  arc A9 (-36, -15.5) -> (-39, -12.5) centre (-39, -15.5) ccw
  point P0 (0, 0)
  point P1 (-36, -12.5)
  point P2 (-42, -27.5)
  point P3 (-42, -12.5)
  point P4 (-36, -27.5)
  dimension "d42" = 4
  dimension "d105" = 6
  dimension "d106" = 15
  dimension "d107" = 7
  dimension "d108" = 3
  constraints: 8 end point, 8 point on circle, 8 point on line, 8 tangent, 7 centre point, 5 equal radius, 2 parallel, 1 horizontal, 1 perpendicular, 1 vertical alignment
  measures "d42" diameter of A3
  measures "d105" distance of point (-36, -12.5) point (-42, -12.5)
  measures "d106" distance of point (-36, -27.5) point (-36, -12.5)
  measures "d107" distance between parallel lines of L4 L0
  measures "d108" radius of A6
extrude "Extrusión6" add sketch "Boceto8" along normal up to surface (5.5 mm away) contours A0 | A1 | A2 | A3 | A4 | A5 | A8 A9 L3 A6 A7 L1
sketch "Boceto9" plane through (-6, -8, -1.5) normal (0, 0, 1) x (1, 0, 0)
  circle A0 centre (0, 0) radius 1.1 projected
  circle A1 centre (0, -56) radius 1.05 projected
  circle A2 centre (-36, -56) radius 1.05 projected
  circle A3 centre (0, 0) radius 1
  circle A4 centre (0, -56) radius 1
  circle A5 centre (-36, -56) radius 1
  point P0 (6, 8)
  dimension "d43" = 0.1
  constraints: 3 centre point, 2 equal radius
  measures "d43" radial gap between concentric circles of A0 A3
extrude "Extrusión7" add sketch "Boceto9" along normal blind 8 contours A3 | A4 | A5
sketch "Boceto12" plane through (-49.9, -1.5, 20) normal (0, 1, 0) x (1, 0, 0)
  line L0 (8.31, 18.5) -> (14.09, 18.5) projected
  arc A0 (8.31, 18.5) -> (8.31, 15.86) centre (8.31, 17.18) ccw projected
  line L1 (14.09, 15.86) -> (8.31, 15.86) projected
  arc A1 (14.09, 15.86) -> (14.09, 18.5) centre (14.09, 17.18) ccw projected
  arc A2 (14.09, 15.9) -> (14.09, 18.46) centre (14.09, 17.18) ccw projected
  line L2 (8.31, 15.9) -> (14.09, 15.9) projected
  arc A3 (8.31, 18.46) -> (8.31, 15.9) centre (8.31, 17.18) ccw projected
  line L3 (14.09, 18.46) -> (8.31, 18.46) projected
  line L4 (14.09, 19.3) -> (8.31, 19.3)
  arc A4 (8.31, 19.3) -> (8.31, 15.06) centre (8.31, 17.18) ccw
  line L5 (8.31, 15.06) -> (14.09, 15.06)
  arc A5 (14.09, 15.06) -> (14.09, 19.3) centre (14.09, 17.18) ccw
  point P0 (49.9, 20)
  dimension "d65" = 0.8
  constraints: 4 end point, 4 point on circle, 2 centre point, 3 other
  measures "d65" distance between parallel lines of L0 L4
extrude "Extrusión10" cut sketch "Boceto12" against normal blind 6 contours L0 A1 L1 A0 | L2 A3 L3 A2 | A5 L5 A4 L4
chamfer "Chaflán3" distance 2 distance2 3 4 edges at (-38.7, -1.5, 0.7) (-33.69, -1.5, 2.82) (-38.7, -1.5, 4.94) (-43.71, -1.5, 2.82) measured on face at (-33.19, -1.5, 2.82) measured on face at (-38.7, -1.5, 0.2) measured on face at (-38.7, -1.5, 5.44) measured on face at (-44.21, -1.5, 2.82)
sketch "Boceto13" plane through (0, 0, -8) normal (0, 0, -1) x (-1, 0, 0)
  line L0 (-4.5, -66.5) -> (-0.5, -66.5) projected
  line L1 (-0.5, -66.5) -> (-0.5, -70.5) projected
  line L2 (-0.5, -70.5) -> (48.5, -70.5) projected
  line L3 (48.5, -70.5) -> (48.5, -36.3) projected
  line L4 (48.5, -36.3) -> (49.9, -36.3) projected
  line L5 (49.9, -36.3) -> (49.9, -1.5) projected
  line L6 (49.9, -1.5) -> (-0.5, -1.5) projected
  line L7 (-0.5, -1.5) -> (-0.5, -34.5) projected
  line L8 (-0.5, -34.5) -> (-4.5, -34.5) projected
  line L9 (-4.5, -34.5) -> (-4.5, -66.5) projected
  line L10 (49.9, -1.5) -> (-0.5, -1.5)
  line L11 (-4.5, -5.5) -> (-4.5, -57.7854)
  line L12 (2.5534, -70.5) -> (49.9, -70.5)
  line L13 (49.9, -70.5) -> (49.9, -1.5)
  line L14 (-4.5, -66.5) -> (-4.5, -34.5) projected
  line L15 (-4.5, -57.7854) -> (49.9, -57.7854) construction
  line L16 (22.7, -57.7854) -> (22.7, -80.5) construction
  line L17 (-0.5, -66.5) -> (49.9, -66.5)
  arc A0 (-4.5, -66.5) -> (49.9, -66.5) centre (22.7, 23.98) ccw
  arc A1 (-0.5, -1.5) -> (-4.5, -5.5) centre (-0.5, -5.5) ccw
  line L18 (-0.5, -1.5) -> (49.9, -1.5) projected
  arc A2 (49.9, -5.5) -> (45.9, -1.5) centre (45.9, -5.5) ccw
  circle A3 centre (1.5, -61.9227) radius 6
  circle A4 centre (43.9, -61.9227) radius 6
  point P0 (0, 0)
  point P1 (-0.5, -67.6073)
  point P2 (40.3337, -70.5)
  point P3 (5.0663, -70.5)
  point P4 (22.7, -70.5)
  point P5 (48.5, -66.9091)
  point P6 (48.5, -66.5)
  point P7 (22.7, -70.5)
  point P8 (-4.5, -61.9227)
  point P9 (0.0624, -67.7479)
  point P10 (49.9, -61.9227)
  point P11 (48.5, -65.775)
  point P12 (45.9, -1.5)
  point P13 (45.3376, -67.7479)
  dimension "d78" = 10
  dimension "d86" = 12
  constraints: 14 end point, 7 point on circle, 6 point on line, 5 centre point, 5 tangent, 4 symmetric about line, 3 perpendicular, 2 parallel, 1 horizontal, 1 midpoint, 1 vertical, 2 other
  measures "d78" distance from line of L16.end L2
  measures "d86" diameter of A3
extrude "Extrusión11" add sketch "Boceto13" against normal up to surface (28 mm away) contours L0 A3 L1 A0 | L0 L1 A3 | A0 L2 L1 | L1 A3 A0 | L17 A3 L1 | A3 L17 A4 A0 | L11 A1 L7 L8 | L17 A4 | L3 A0 L13 L12 | A4 L17 L3 A0 | A4 L3 | L3 L4 L13 A4 | L3 L17 A0 | L3 A4 L13 L17
extrude "Extrusión14" cut sketch "Boceto13" against normal through all contours L9 A3 L0 | L0 A3 L1 A0 | A0 L2 L1 | L1 A3 A0 | A0 L3 L2 | L3 A0 L13 L12 | A4 L17 L3 A0 | A4 L3 L17 | L3 L17 A0 | L3 A4 L13 L17 | L6 L5 A2 picked at (48.2689, -66.2674)
sketch "Boceto18" plane through (0, 0, 20) normal (0, 0, 1) x (1, 0, 0)
  arc A0 (-0.0624, -67.7479) -> (4.5, -61.9227) centre (-1.5, -61.9227) ccw projected
  line L0 (4.5, -61.9227) -> (4.5, -5.5) projected
  arc A1 (4.5, -5.5) -> (0.5, -1.5) centre (0.5, -5.5) ccw projected
  line L1 (0.5, -1.5) -> (-45.9, -1.5) projected
  arc A2 (-45.9, -1.5) -> (-49.9, -5.5) centre (-45.9, -5.5) ccw projected
  line L2 (-49.9, -5.5) -> (-49.9, -61.9227) projected
  arc A3 (-49.9, -61.9227) -> (-45.3376, -67.7479) centre (-43.9, -61.9227) ccw projected
  arc A4 (-45.3376, -67.7479) -> (-0.0624, -67.7479) centre (-22.7, 23.98) ccw projected
  line L3 (-44.5, -66.5) -> (-44.5, -33.8) projected
  line L4 (-44.5, -33.8) -> (-48.5, -33.8) projected
  line L5 (-48.5, -33.8) -> (-48.5, -5.5) projected
  line L6 (-48.5, -5.5) -> (-3.5, -5.5) projected
  line L7 (-3.5, -5.5) -> (-3.5, -37.5) projected
  line L8 (-3.5, -37.5) -> (0.5, -37.5) projected
  line L9 (0.5, -37.5) -> (0.5, -63.5) projected
  line L10 (0.5, -63.5) -> (-3.5, -63.5) projected
  line L11 (-3.5, -63.5) -> (-3.5, -66.5) projected
  line L12 (-3.5, -66.5) -> (-44.5, -66.5) projected
  arc A5 (-0.5416, -65.8062) -> (2.5, -61.9227) centre (-1.5, -61.9227) ccw
  line L13 (2.5, -61.9227) -> (2.5, -5.5)
  arc A6 (2.5, -5.5) -> (0.5, -3.5) centre (0.5, -5.5) ccw
  line L14 (0.5, -3.5) -> (-45.9, -3.5)
  arc A7 (-45.9, -3.5) -> (-47.9, -5.5) centre (-45.9, -5.5) ccw
  line L15 (-47.9, -5.5) -> (-47.9, -61.9227)
  arc A8 (-47.9, -61.9227) -> (-44.8584, -65.8062) centre (-43.9, -61.9227) ccw
  arc A9 (-44.8584, -65.8062) -> (-0.5416, -65.8062) centre (-22.7, 23.98) ccw
  line L16 (-15.5, -3.5) -> (-25.5, -3.5)
  line L17 (-25.5, -3.5) -> (-25.5, -1.5)
  line L18 (-25.5, -1.5) -> (-15.5, -1.5)
  line L19 (-15.5, -1.5) -> (-15.5, -3.5)
  point P0 (0, 0)
  point P1 (-3.5, -66.485)
  point P2 (-3.571, -66.5)
  dimension "d109" = 2
  dimension "d110" = 10
  dimension "d111" = 20
  constraints: 14 end point, 10 point on circle, 5 centre point, 2 parallel, 2 point on line, 1 horizontal, 1 perpendicular, 7 other
  measures "d109" radial gap between concentric circles of A4 A9
  measures "d110" distance between parallel lines of L19 L17
  measures "d111" distance between parallel lines of L0 L19
extrude "Extrusión16" add sketch "Boceto18" along normal blind 3 contours A4 A3 L2 A2 L1 L17 L14 A7 L6 L5 L4 L15 A8 A9 L3 L12 L11 A5 L13 A6 L19 A1 L0 A0 | L19 L14 L17 L1 | L15 L4 L5 L6 | L11 L12 A9 | A9 L12 L3
sketch "Boceto19" plane through (0, 0, 0) normal (1, 0, 0) x (0, 1, 0)
  line L0 (-3.5, 20) -> (-3.5, 23) projected
  arc A0 (-3.5, 20) -> (-3.5, 23) centre (-4.5063, 21.5) ccw
  point P0 (0, 0)
  point P1 (-2.7, 21.5)
  dimension "d114" = 0.8
  constraints: 3 point on circle, 1 centre point
  measures "d114" distance from line of L0 point (-2.7, 21.5)
sketch3d "Boceto 3D4"
  line L0 (0.5, -3.5, 23) -> (-45.9, -3.5, 23)
  arc A0 (-45.9, -3.5, 23) -> (-47.9, -5.5, 23) centre (-45.9, -5.5, 23) ccw
  line L1 (-47.9, -5.5, 23) -> (-47.9, -61.9227, 23)
  arc A1 (-47.9, -61.9227, 23) -> (-44.8584, -65.8062, 23) centre (-43.9, -61.9227, 23) ccw
  arc A2 (-44.8584, -65.8062, 23) -> (-0.5416, -65.8062, 23) centre (-22.7, 23.98, 23) ccw
  arc A3 (-0.5416, -65.8062, 23) -> (2.5, -61.9227, 23) centre (-1.5, -61.9227, 23) ccw
  line L2 (2.5, -61.9227, 23) -> (2.5, -5.5, 23)
  arc A4 (2.5, -5.5, 23) -> (0.5, -3.5, 23) centre (0.5, -5.5, 23) ccw
sweep "Barrido4" cut profiles "Boceto19" path "Boceto 3D4"
chamfer "Chaflán4" distance 0.1 angle 45 8 edges at (2.5, -33.7113, 23) (1.6491, -64.3891, 23) (-22.7, -68.5, 23) (-47.0491, -64.3891, 23) (-47.9, -33.7113, 23) (-47.3142, -4.0858, 23) (-22.7, -3.5, 23) (1.9142, -4.0858, 23)
fillet "Empalme8" radius 3 1 edges at (-48.5, -19.65, -7)
sketch "Boceto22" plane through (0, 0, -8) normal (0, 0, -1) x (-1, 0, 0)
  arc A0 (49.9, -5.5) -> (45.9, -1.5) centre (45.9, -5.5) ccw projected
  line L0 (49.9, -5.5) -> (49.9, -61.9227) projected
  arc A1 (45.3376, -67.7479) -> (49.9, -61.9227) centre (43.9, -61.9227) ccw projected
  arc A2 (0.0624, -67.7479) -> (45.3376, -67.7479) centre (22.7, 23.98) ccw projected
  arc A3 (-4.5, -61.9227) -> (0.0624, -67.7479) centre (1.5, -61.9227) ccw projected
  line L1 (-4.5, -61.9227) -> (-4.5, -5.5) projected
  arc A4 (-0.5, -1.5) -> (-4.5, -5.5) centre (-0.5, -5.5) ccw projected
  line L2 (-0.5, -1.5) -> (45.9, -1.5) projected
  point P0 (0, 0)
extrude "Extrusión19" add sketch "Boceto22" along normal blind 1.5
chamfer "Chaflán5" distance 2 distance2 3 8 edges at (-22.7, -1.5, -9.5) (3.3284, -2.6716, -9.5) (4.5, -33.7113, -9.5) (3.2236, -65.6223, -9.5) (-22.7, -70.5, -9.5) (-48.6236, -65.6223, -9.5) (-49.9, -33.7113, -9.5) (-48.7284, -2.6716, -9.5) measured on face at (2.83, -65.314, -9.5) measured on face at (-48.23, -65.314, -9.5) measured on face at (4, -33.7113, -9.5) measured on face at (-48.3749, -3.0251, -9.5) measured on face at (-22.7, -70, -9.5) measured on face at (-49.4, -33.7113, -9.5) measured on face at (-22.7, -2, -9.5) measured on face at (2.9749, -3.0251, -9.5)